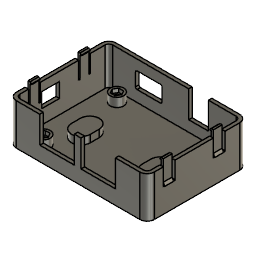
BaseCase (Autodesk Fusion 360 design; units mm, degrees)
part number: 2026-10-22-00-47-47-344
Autodesk Fusion 360 part; units mm, degrees
sketch "01 Contur exterior 94 x 68 R5" plane through (0, 0, 0) normal (0, 0, 1) x (1, 0, 0)
  line L0 (5, 0) -> (89, 0)
  line L1 (94, 5) -> (94, 63)
  line L2 (89, 68) -> (5, 68)
  line L3 (0, 63) -> (0, 5)
  arc A0 (89, 0) -> (94, 5) centre (89, 5) ccw
  arc A1 (94, 63) -> (89, 68) centre (89, 63) ccw
  arc A2 (5, 68) -> (0, 63) centre (5, 63) ccw
  arc A3 (0, 5) -> (5, 0) centre (5, 5) ccw
extrude "01 Corp exterior" add sketch "01 Contur exterior 94 x 68 R5" along normal blind 28
ref_plane "WorkPlane1" through (0, 0, 2.4) normal (0, 0, 1) x (1, 0, 0)
sketch "02 Cavitate - pereti 2.4 mm" plane through (0, 0, 2.4) normal (0, 0, 1) x (1, 0, 0)
  line L0 (5, 2.4) -> (89, 2.4)
  line L1 (91.6, 5) -> (91.6, 63)
  line L2 (89, 65.6) -> (5, 65.6)
  line L3 (2.4, 63) -> (2.4, 5)
  arc A0 (89, 2.4) -> (91.6, 5) centre (89, 5) ccw
  arc A1 (91.6, 63) -> (89, 65.6) centre (89, 63) ccw
  arc A2 (5, 65.6) -> (2.4, 63) centre (5, 63) ccw
  arc A3 (2.4, 5) -> (5, 2.4) centre (5, 5) ccw
extrude "02 Gol interior" cut sketch "02 Cavitate - pereti 2.4 mm" along normal blind 28
ref_plane "WorkPlane2" through (0, 0, 2.4) normal (0, 0, 1) x (1, 0, 0)
sketch "03 Suporturi PCB" plane through (0, 0, 2.4) normal (0, 0, 1) x (1, 0, 0)
  circle A0 centre (14.5, 59) radius 4.6
  circle A1 centre (79.5, 59) radius 4.6
  circle A2 centre (14.5, 9) radius 4.6
  circle A3 centre (79.5, 9) radius 4.6
extrude "03 Suporturi PCB (1)" add sketch "03 Suporturi PCB" along normal blind 6
ref_plane "WorkPlane3" through (0, 0, 5.8) normal (0, 0, 1) x (1, 0, 0)
sketch "04 Locasuri piulite M3 AF5.7" plane through (0, 0, 5.8) normal (0, 0, 1) x (1, 0, 0)
  line L0 (17.7909, 59) -> (16.1454, 61.85)
  line L1 (16.1454, 61.85) -> (12.8546, 61.85)
  line L2 (12.8546, 61.85) -> (11.2091, 59)
  line L3 (11.2091, 59) -> (12.8546, 56.15)
  line L4 (12.8546, 56.15) -> (16.1454, 56.15)
  line L5 (16.1454, 56.15) -> (17.7909, 59)
  line L6 (82.7909, 59) -> (81.1454, 61.85)
  line L7 (81.1454, 61.85) -> (77.8546, 61.85)
  line L8 (77.8546, 61.85) -> (76.2091, 59)
  line L9 (76.2091, 59) -> (77.8546, 56.15)
  line L10 (77.8546, 56.15) -> (81.1454, 56.15)
  line L11 (81.1454, 56.15) -> (82.7909, 59)
  line L12 (17.7909, 9) -> (16.1454, 11.85)
  line L13 (16.1454, 11.85) -> (12.8546, 11.85)
  line L14 (12.8546, 11.85) -> (11.2091, 9)
  line L15 (11.2091, 9) -> (12.8546, 6.15)
  line L16 (12.8546, 6.15) -> (16.1454, 6.15)
  line L17 (16.1454, 6.15) -> (17.7909, 9)
  line L18 (82.7909, 9) -> (81.1454, 11.85)
  line L19 (81.1454, 11.85) -> (77.8546, 11.85)
  line L20 (77.8546, 11.85) -> (76.2091, 9)
  line L21 (76.2091, 9) -> (77.8546, 6.15)
  line L22 (77.8546, 6.15) -> (81.1454, 6.15)
  line L23 (81.1454, 6.15) -> (82.7909, 9)
extrude "04 Piulite PCB" cut sketch "04 Locasuri piulite M3 AF5.7" along normal blind 2.8
ref_plane "WorkPlane4" through (0, 0, 3.2) normal (0, 0, 1) x (1, 0, 0)
sketch "05 Gauri PCB diametru 3.4" plane through (0, 0, 3.2) normal (0, 0, 1) x (1, 0, 0)
  circle A0 centre (14.5, 59) radius 1.7
  circle A1 centre (79.5, 59) radius 1.7
  circle A2 centre (14.5, 9) radius 1.7
  circle A3 centre (79.5, 9) radius 1.7
extrude "05 Gauri PCB diametru 3.4 (1)" cut sketch "05 Gauri PCB diametru 3.4" along normal blind 12
ref_plane "WorkPlane5" through (0, 0, 2.4) normal (0, 0, 1) x (1, 0, 0)
sketch "06 Protectii prindere perete" plane through (0, 0, 2.4) normal (0, 0, 1) x (1, 0, 0)
  line L0 (29.4, 26) -> (29.4, 32)
  arc A0 (29.4, 32) -> (16.6, 32) centre (23, 32) ccw
  line L1 (16.6, 32) -> (16.6, 26)
  arc A1 (16.6, 26) -> (29.4, 26) centre (23, 26) ccw
  line L2 (77.4, 26) -> (77.4, 32)
  arc A2 (77.4, 32) -> (64.6, 32) centre (71, 32) ccw
  line L3 (64.6, 32) -> (64.6, 26)
  arc A3 (64.6, 26) -> (77.4, 26) centre (71, 26) ccw
extrude "06 Capace prindere perete" add sketch "06 Protectii prindere perete" along normal blind 5
ref_plane "WorkPlane6" through (0, 0, 2.4) normal (0, 0, 1) x (1, 0, 0)
sketch "07 Cavitati cap surub" plane through (0, 0, 2.4) normal (0, 0, 1) x (1, 0, 0)
  line L0 (27.6, 26) -> (27.6, 32)
  arc A0 (27.6, 32) -> (18.4, 32) centre (23, 32) ccw
  line L1 (18.4, 32) -> (18.4, 26)
  arc A1 (18.4, 26) -> (27.6, 26) centre (23, 26) ccw
  line L2 (75.6, 26) -> (75.6, 32)
  arc A2 (75.6, 32) -> (66.4, 32) centre (71, 32) ccw
  line L3 (66.4, 32) -> (66.4, 26)
  arc A3 (66.4, 26) -> (75.6, 26) centre (71, 26) ccw
extrude "07 Spatiu cap surub perete" cut sketch "07 Cavitati cap surub" along normal blind 3.6
sketch "08 Intrari cap surub" plane through (0, 0, 0) normal (0, 0, 1) x (1, 0, 0)
  circle A0 centre (23, 26) radius 4.25
  circle A1 centre (71, 26) radius 4.25
extrude "08 Intrari cap surub (1)" cut sketch "08 Intrari cap surub" along normal blind 2.5
sketch "09 Fante prindere perete" plane through (0, 0, 0) normal (0, 0, 1) x (1, 0, 0)
  line L0 (25.2, 26) -> (25.2, 32)
  arc A0 (25.2, 32) -> (20.8, 32) centre (23, 32) ccw
  line L1 (20.8, 32) -> (20.8, 26)
  arc A1 (20.8, 26) -> (25.2, 26) centre (23, 26) ccw
  line L2 (73.2, 26) -> (73.2, 32)
  arc A2 (73.2, 32) -> (68.8, 32) centre (71, 32) ccw
  line L3 (68.8, 32) -> (68.8, 26)
  arc A3 (68.8, 26) -> (73.2, 26) centre (71, 26) ccw
extrude "09 Fante 4.4 mm" cut sketch "09 Fante prindere perete" along normal blind 2.5
ref_plane "WorkPlane7" through (0, 0, 9.8) normal (0, 0, 1) x (1, 0, 0)
sketch "10 Acces borne LED si alimentare" plane through (0, 0, 9.8) normal (0, 0, 1) x (1, 0, 0)
  line L0 (21, -1) -> (44.5, -1)
  line L1 (44.5, -1) -> (44.5, 16)
  line L2 (44.5, 16) -> (21, 16)
  line L3 (21, 16) -> (21, -1)
  line L4 (49, -1) -> (72.5, -1)
  line L5 (72.5, -1) -> (72.5, 16)
  line L6 (72.5, 16) -> (49, 16)
  line L7 (49, 16) -> (49, -1)
  line L8 (56.7, 52) -> (70, 52)
  line L9 (70, 52) -> (70, 69)
  line L10 (70, 69) -> (56.7, 69)
  line L11 (56.7, 69) -> (56.7, 52)
extrude "10 Acces borne LED si alimentare (1)" cut sketch "10 Acces borne LED si alimentare" along normal blind 28
ref_plane "WorkPlane8" through (0, 71, 0) normal (0, 1, 0) x (0, 0, 1)
sketch "11 USB-C 18 x 11 R1" plane through (0, 71, 0) normal (0, 1, 0) x (1, 0, 0)
  line L0 (21.5, -10) -> (37.5, -10)
  line L1 (38.5, -11) -> (38.5, -20)
  line L2 (37.5, -21) -> (21.5, -21)
  line L3 (20.5, -20) -> (20.5, -11)
  arc A0 (38.5, -11) -> (37.5, -10) centre (37.5, -11) ccw
  arc A1 (37.5, -21) -> (38.5, -20) centre (37.5, -20) ccw
  arc A2 (20.5, -20) -> (21.5, -21) centre (21.5, -20) ccw
  arc A3 (21.5, -10) -> (20.5, -11) centre (21.5, -11) ccw
extrude "11 Fereastra USB-C" cut sketch "11 USB-C 18 x 11 R1" against normal blind 8
ref_plane "WorkPlane9" through (0, 0, 12) normal (0, 0, 1) x (1, 0, 0)
sketch "12 Iesire cablu IR" plane through (0, 0, 12) normal (0, 0, 1) x (1, 0, 0)
  line L0 (-1, 20) -> (4, 20)
  line L1 (4, 20) -> (4, 32)
  line L2 (4, 32) -> (-1, 32)
  line L3 (-1, 32) -> (-1, 20)
extrude "12 Iesire cablu IR (1)" cut sketch "12 Iesire cablu IR" along normal blind 10
ref_plane "WorkPlane10" through (0, 0, 16.5) normal (0, 0, 1) x (1, 0, 0)
sketch "13 Fanta Stanga11.5" plane through (0, 0, 16.5) normal (0, 0, 1) x (1, 0, 0)
  line L0 (-1, 11) -> (3, 11)
  line L1 (3, 11) -> (3, 12)
  line L2 (3, 12) -> (-1, 12)
  line L3 (-1, 12) -> (-1, 11)
extrude "13 Fanta Stanga11.5 (1)" cut sketch "13 Fanta Stanga11.5" along normal blind 18
ref_plane "WorkPlane11" through (-1, 0, 0) normal (1, 0, 0) x (0, 1, 0)
sketch "14 Racord fanta Stanga11.5" plane through (-1, 0, 0) normal (1, 0, 0) x (0, 0, -1)
  circle A0 centre (-16.5, 11.5) radius 0.5
extrude "14 Radacina rotunjita Stanga11.5" cut sketch "14 Racord fanta Stanga11.5" along normal blind 4
ref_plane "WorkPlane12" through (0, 0, 16.5) normal (0, 0, 1) x (1, 0, 0)
sketch "13 Fanta Stanga18.5" plane through (0, 0, 16.5) normal (0, 0, 1) x (1, 0, 0)
  line L0 (-1, 18) -> (3, 18)
  line L1 (3, 18) -> (3, 19)
  line L2 (3, 19) -> (-1, 19)
  line L3 (-1, 19) -> (-1, 18)
extrude "13 Fanta Stanga18.5 (1)" cut sketch "13 Fanta Stanga18.5" along normal blind 18
ref_plane "WorkPlane13" through (-1, 0, 0) normal (1, 0, 0) x (0, 1, 0)
sketch "14 Racord fanta Stanga18.5" plane through (-1, 0, 0) normal (1, 0, 0) x (0, 0, -1)
  circle A0 centre (-16.5, 18.5) radius 0.5
extrude "14 Radacina rotunjita Stanga18.5" cut sketch "14 Racord fanta Stanga18.5" along normal blind 4
ref_plane "WorkPlane14" through (0, 18, 0) normal (0, 1, 0) x (0, 0, 1)
sketch "15 Profil elastic Stanga15" plane through (0, 18, 0) normal (0, 1, 0) x (1, 0, 0)
  line L0 (-1, -16) -> (0, -16)
  line L1 (0, -16) -> (1, -18)
  line L2 (1, -18) -> (1, -33)
  line L3 (1, -33) -> (-1, -33)
  line L4 (-1, -33) -> (-1, -16)
extrude "15 Subtiere clips Stanga15" cut sketch "15 Profil elastic Stanga15" against normal blind 6
ref_plane "WorkPlane15" through (0, 18, 0) normal (0, 1, 0) x (0, 0, 1)
sketch "16 Carlig Stanga15" plane through (0, 18, 0) normal (0, 1, 0) x (1, 0, 0)
  line L0 (1, -27.9) -> (2.4, -27.9)
  line L1 (2.4, -27.9) -> (2.4, -30.6)
  line L2 (2.4, -30.6) -> (3.4, -30.6)
  line L3 (3.4, -30.6) -> (3.4, -31)
  line L4 (3.4, -31) -> (2.4, -31.8)
  line L5 (2.4, -31.8) -> (1, -31.8)
  line L6 (1, -31.8) -> (1, -27.9)
extrude "16 Carlig clips Stanga15" add sketch "16 Carlig Stanga15" against normal blind 6
ref_plane "WorkPlane16" through (0, 0, 16.5) normal (0, 0, 1) x (1, 0, 0)
sketch "13 Fanta Stanga45.5" plane through (0, 0, 16.5) normal (0, 0, 1) x (1, 0, 0)
  line L0 (-1, 45) -> (3, 45)
  line L1 (3, 45) -> (3, 46)
  line L2 (3, 46) -> (-1, 46)
  line L3 (-1, 46) -> (-1, 45)
extrude "13 Fanta Stanga45.5 (1)" cut sketch "13 Fanta Stanga45.5" along normal blind 18
ref_plane "WorkPlane17" through (-1, 0, 0) normal (1, 0, 0) x (0, 1, 0)
sketch "14 Racord fanta Stanga45.5" plane through (-1, 0, 0) normal (1, 0, 0) x (0, 0, -1)
  circle A0 centre (-16.5, 45.5) radius 0.5
extrude "14 Radacina rotunjita Stanga45.5" cut sketch "14 Racord fanta Stanga45.5" along normal blind 4
ref_plane "WorkPlane18" through (0, 0, 16.5) normal (0, 0, 1) x (1, 0, 0)
sketch "13 Fanta Stanga52.5" plane through (0, 0, 16.5) normal (0, 0, 1) x (1, 0, 0)
  line L0 (-1, 52) -> (3, 52)
  line L1 (3, 52) -> (3, 53)
  line L2 (3, 53) -> (-1, 53)
  line L3 (-1, 53) -> (-1, 52)
extrude "13 Fanta Stanga52.5 (1)" cut sketch "13 Fanta Stanga52.5" along normal blind 18
ref_plane "WorkPlane19" through (-1, 0, 0) normal (1, 0, 0) x (0, 1, 0)
sketch "14 Racord fanta Stanga52.5" plane through (-1, 0, 0) normal (1, 0, 0) x (0, 0, -1)
  circle A0 centre (-16.5, 52.5) radius 0.5
extrude "14 Radacina rotunjita Stanga52.5" cut sketch "14 Racord fanta Stanga52.5" along normal blind 4
ref_plane "WorkPlane20" through (0, 52, 0) normal (0, 1, 0) x (0, 0, 1)
sketch "15 Profil elastic Stanga49" plane through (0, 52, 0) normal (0, 1, 0) x (1, 0, 0)
  line L0 (-1, -16) -> (0, -16)
  line L1 (0, -16) -> (1, -18)
  line L2 (1, -18) -> (1, -33)
  line L3 (1, -33) -> (-1, -33)
  line L4 (-1, -33) -> (-1, -16)
extrude "15 Subtiere clips Stanga49" cut sketch "15 Profil elastic Stanga49" against normal blind 6
ref_plane "WorkPlane21" through (0, 52, 0) normal (0, 1, 0) x (0, 0, 1)
sketch "16 Carlig Stanga49" plane through (0, 52, 0) normal (0, 1, 0) x (1, 0, 0)
  line L0 (1, -27.9) -> (2.4, -27.9)
  line L1 (2.4, -27.9) -> (2.4, -30.6)
  line L2 (2.4, -30.6) -> (3.4, -30.6)
  line L3 (3.4, -30.6) -> (3.4, -31)
  line L4 (3.4, -31) -> (2.4, -31.8)
  line L5 (2.4, -31.8) -> (1, -31.8)
  line L6 (1, -31.8) -> (1, -27.9)
extrude "16 Carlig clips Stanga49" add sketch "16 Carlig Stanga49" against normal blind 6
ref_plane "WorkPlane22" through (0, 0, 16.5) normal (0, 0, 1) x (1, 0, 0)
sketch "13 Fanta Dreapta11.5" plane through (0, 0, 16.5) normal (0, 0, 1) x (1, 0, 0)
  line L0 (91, 11) -> (95, 11)
  line L1 (95, 11) -> (95, 12)
  line L2 (95, 12) -> (91, 12)
  line L3 (91, 12) -> (91, 11)
extrude "13 Fanta Dreapta11.5 (1)" cut sketch "13 Fanta Dreapta11.5" along normal blind 18
ref_plane "WorkPlane23" through (91, 0, 0) normal (1, 0, 0) x (0, 1, 0)
sketch "14 Racord fanta Dreapta11.5" plane through (91, 0, 0) normal (1, 0, 0) x (0, 0, -1)
  circle A0 centre (-16.5, 11.5) radius 0.5
extrude "14 Radacina rotunjita Dreapta11.5" cut sketch "14 Racord fanta Dreapta11.5" along normal blind 4
ref_plane "WorkPlane24" through (0, 0, 16.5) normal (0, 0, 1) x (1, 0, 0)
sketch "13 Fanta Dreapta18.5" plane through (0, 0, 16.5) normal (0, 0, 1) x (1, 0, 0)
  line L0 (91, 18) -> (95, 18)
  line L1 (95, 18) -> (95, 19)
  line L2 (95, 19) -> (91, 19)
  line L3 (91, 19) -> (91, 18)
extrude "13 Fanta Dreapta18.5 (1)" cut sketch "13 Fanta Dreapta18.5" along normal blind 18
ref_plane "WorkPlane25" through (91, 0, 0) normal (1, 0, 0) x (0, 1, 0)
sketch "14 Racord fanta Dreapta18.5" plane through (91, 0, 0) normal (1, 0, 0) x (0, 0, -1)
  circle A0 centre (-16.5, 18.5) radius 0.5
extrude "14 Radacina rotunjita Dreapta18.5" cut sketch "14 Racord fanta Dreapta18.5" along normal blind 4
ref_plane "WorkPlane26" through (0, 18, 0) normal (0, 1, 0) x (0, 0, 1)
sketch "15 Profil elastic Dreapta15" plane through (0, 18, 0) normal (0, 1, 0) x (1, 0, 0)
  line L0 (95, -16) -> (94, -16)
  line L1 (94, -16) -> (93, -18)
  line L2 (93, -18) -> (93, -33)
  line L3 (93, -33) -> (95, -33)
  line L4 (95, -33) -> (95, -16)
extrude "15 Subtiere clips Dreapta15" cut sketch "15 Profil elastic Dreapta15" against normal blind 6
ref_plane "WorkPlane27" through (0, 18, 0) normal (0, 1, 0) x (0, 0, 1)
sketch "16 Carlig Dreapta15" plane through (0, 18, 0) normal (0, 1, 0) x (1, 0, 0)
  line L0 (93, -27.9) -> (91.6, -27.9)
  line L1 (91.6, -27.9) -> (91.6, -30.6)
  line L2 (91.6, -30.6) -> (90.6, -30.6)
  line L3 (90.6, -30.6) -> (90.6, -31)
  line L4 (90.6, -31) -> (91.6, -31.8)
  line L5 (91.6, -31.8) -> (93, -31.8)
  line L6 (93, -31.8) -> (93, -27.9)
extrude "16 Carlig clips Dreapta15" add sketch "16 Carlig Dreapta15" against normal blind 6
ref_plane "WorkPlane28" through (0, 0, 16.5) normal (0, 0, 1) x (1, 0, 0)
sketch "13 Fanta Dreapta45.5" plane through (0, 0, 16.5) normal (0, 0, 1) x (1, 0, 0)
  line L0 (91, 45) -> (95, 45)
  line L1 (95, 45) -> (95, 46)
  line L2 (95, 46) -> (91, 46)
  line L3 (91, 46) -> (91, 45)
extrude "13 Fanta Dreapta45.5 (1)" cut sketch "13 Fanta Dreapta45.5" along normal blind 18
ref_plane "WorkPlane29" through (91, 0, 0) normal (1, 0, 0) x (0, 1, 0)
sketch "14 Racord fanta Dreapta45.5" plane through (91, 0, 0) normal (1, 0, 0) x (0, 0, -1)
  circle A0 centre (-16.5, 45.5) radius 0.5
extrude "14 Radacina rotunjita Dreapta45.5" cut sketch "14 Racord fanta Dreapta45.5" along normal blind 4
ref_plane "WorkPlane30" through (0, 0, 16.5) normal (0, 0, 1) x (1, 0, 0)
sketch "13 Fanta Dreapta52.5" plane through (0, 0, 16.5) normal (0, 0, 1) x (1, 0, 0)
  line L0 (91, 52) -> (95, 52)
  line L1 (95, 52) -> (95, 53)
  line L2 (95, 53) -> (91, 53)
  line L3 (91, 53) -> (91, 52)
extrude "13 Fanta Dreapta52.5 (1)" cut sketch "13 Fanta Dreapta52.5" along normal blind 18
ref_plane "WorkPlane31" through (91, 0, 0) normal (1, 0, 0) x (0, 1, 0)
sketch "14 Racord fanta Dreapta52.5" plane through (91, 0, 0) normal (1, 0, 0) x (0, 0, -1)
  circle A0 centre (-16.5, 52.5) radius 0.5
extrude "14 Radacina rotunjita Dreapta52.5" cut sketch "14 Racord fanta Dreapta52.5" along normal blind 4
ref_plane "WorkPlane32" through (0, 52, 0) normal (0, 1, 0) x (0, 0, 1)
sketch "15 Profil elastic Dreapta49" plane through (0, 52, 0) normal (0, 1, 0) x (1, 0, 0)
  line L0 (95, -16) -> (94, -16)
  line L1 (94, -16) -> (93, -18)
  line L2 (93, -18) -> (93, -33)
  line L3 (93, -33) -> (95, -33)
  line L4 (95, -33) -> (95, -16)
extrude "15 Subtiere clips Dreapta49" cut sketch "15 Profil elastic Dreapta49" against normal blind 6
ref_plane "WorkPlane33" through (0, 52, 0) normal (0, 1, 0) x (0, 0, 1)
sketch "16 Carlig Dreapta49" plane through (0, 52, 0) normal (0, 1, 0) x (1, 0, 0)
  line L0 (93, -27.9) -> (91.6, -27.9)
  line L1 (91.6, -27.9) -> (91.6, -30.6)
  line L2 (91.6, -30.6) -> (90.6, -30.6)
  line L3 (90.6, -30.6) -> (90.6, -31)
  line L4 (90.6, -31) -> (91.6, -31.8)
  line L5 (91.6, -31.8) -> (93, -31.8)
  line L6 (93, -31.8) -> (93, -27.9)
extrude "16 Carlig clips Dreapta49" add sketch "16 Carlig Dreapta49" against normal blind 6
equation "Wall = 2.4 mm" comment "Octoglow nominal dimension"
equation "BaseHeight = 28 mm" comment "Octoglow nominal dimension"
equation "LidThickness = 2.4 mm" comment "Octoglow nominal dimension"
equation "LogoRelief = 0.6 mm" comment "Octoglow nominal dimension"
equation "d5 = BaseHeight"
named bodies: "Octoglow_Baza_Clips"
